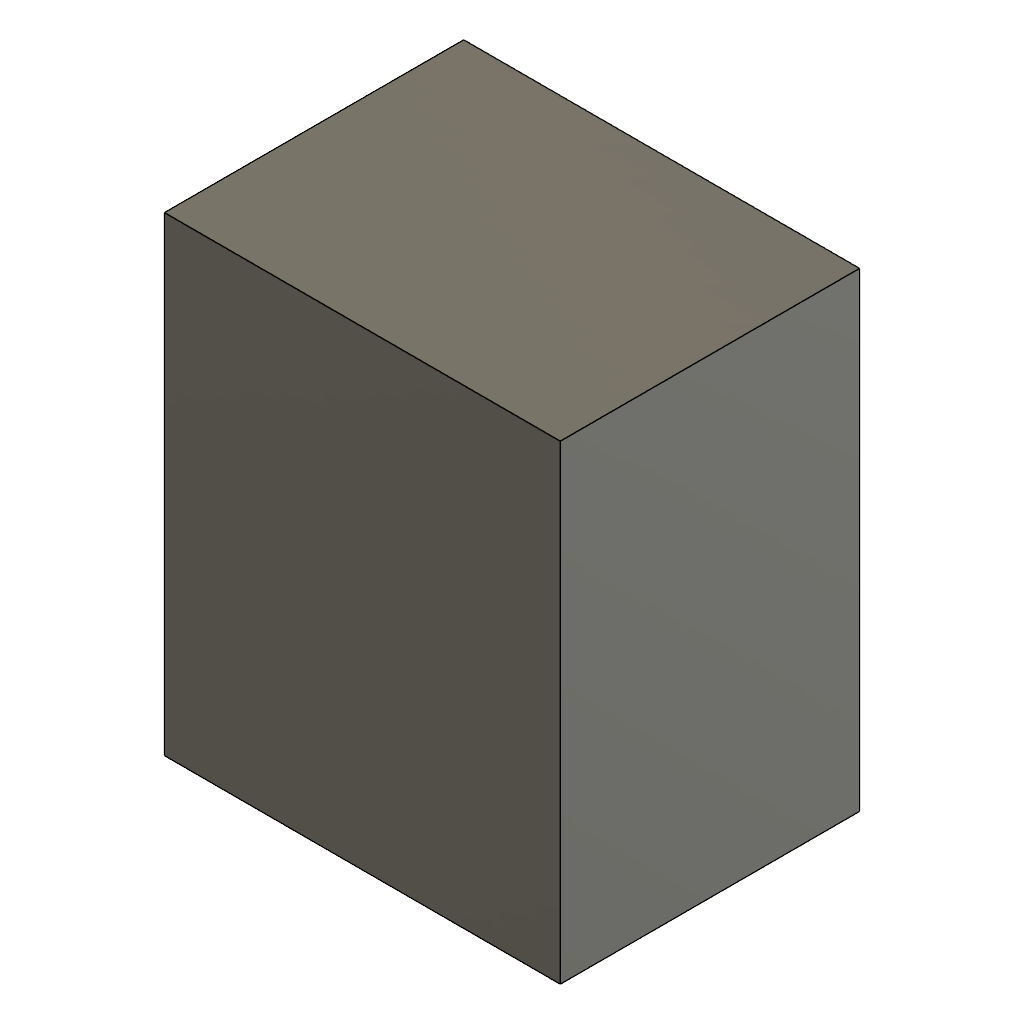
HeldOutSide (Autodesk Fusion 360 design; units mm, degrees)
part number: 2026-11-22-13-36-51-479
Autodesk Fusion 360 part; units mm, degrees
sketch "Base sketch" plane through (0, 0, 0) normal (0, 0, 1) x (1, 0, 0)
  line L0 (-13, -7) -> (28, -7)
  line L1 (28, -7) -> (28, 39)
  line L2 (28, 39) -> (-13, 39)
  line L3 (-13, 39) -> (-13, -7)
extrude "Base" add sketch "Base sketch" along normal blind 31
move_face "Measured face offset" offset 2.7 1 faces at (0.6667, -7, 10.3333)
